Autodesk Fusion 360 part; units mm, degrees
(part 2 of 3)
  spline S78 degree 3 poles (62.3363, -64.3486) (62.4149, -64.4998) (62.5733, -64.8047) (62.5949, -65.1477) (62.6057, -65.3206) knots 0 0 0 0 0.050517 0.101865 0.101865 0.101865 0.101865
  spline S79 degree 3 poles (62.6057, -65.3206) (62.5968, -65.4784) (62.5791, -65.7914) (62.4487, -66.0764) (62.384, -66.2176) knots 0 0 0 0 0.046969 0.093127 0.093127 0.093127 0.093127
  spline S80 degree 3 poles (62.384, -66.2176) (62.3034, -66.3494) (62.1421, -66.613) (61.901, -66.8064) (61.7804, -66.9031) knots 0 0 0 0 0.045957 0.091962 0.091962 0.091962 0.091962
  spline S81 degree 3 poles (61.7804, -66.9031) (61.6697, -66.9728) (61.4254, -67.1265) (61.1499, -67.2136) (60.9993, -67.2613) knots 0 0 0 0 0.039078 0.086233 0.086233 0.086233 0.086233
  spline S82 degree 3 poles (60.9993, -67.2613) (60.8294, -67.304) (60.4812, -67.3916) (60.1223, -67.4024) (59.9386, -67.4079) knots 0 0 0 0 0.052412 0.10736 0.10736 0.10736 0.10736
  spline S83 degree 3 poles (59.9386, -67.4079) (59.6696, -67.4001) (59.1592, -67.3852) (58.6718, -67.2339) (58.4413, -67.1623) knots 0 0 0 0 0.0803 0.152356 0.152356 0.152356 0.152356
  spline S84 degree 3 poles (58.4413, -67.1623) (58.2451, -67.0792) (57.88, -66.9245) (57.6132, -66.6324) (57.4898, -66.4973) knots 0 0 0 0 0.063037 0.117311 0.117311 0.117311 0.117311
  spline S85 degree 3 poles (57.4898, -66.4973) (57.3942, -66.3374) (57.1861, -65.9894) (57.1087, -65.5907) (57.0668, -65.3752) knots 0 0 0 0 0.055458 0.120727 0.120727 0.120727 0.120727
  line L43 (57.0668, -65.3752) -> (58.2674, -65.2115)
  spline S86 degree 3 poles (58.2674, -65.2115) (58.3053, -65.3858) (58.3788, -65.7235) (58.6233, -65.9669) (58.7415, -66.0846) knots 0 0 0 0 0.052286 0.10125 0.10125 0.10125 0.10125
  spline S87 degree 3 poles (58.7415, -66.0846) (58.8953, -66.1759) (59.2356, -66.3778) (59.6325, -66.3911) (59.8499, -66.3984) knots 0 0 0 0 0.052851 0.116857 0.116857 0.116857 0.116857
  spline S88 degree 3 poles (59.8499, -66.3984) (60.097, -66.3964) (60.5227, -66.3929) (60.8993, -66.1997) (61.0573, -66.1187) knots 0 0 0 0 0.072813 0.125434 0.125434 0.125434 0.125434
  spline S89 degree 3 poles (61.0573, -66.1187) (61.1626, -66.0255) (61.3619, -65.8492) (61.4006, -65.5873) (61.4188, -65.4638) knots 0 0 0 0 0.040702 0.076975 0.076975 0.076975 0.076975
  spline S90 degree 3 poles (61.4188, -65.4638) (61.4125, -65.3861) (61.3997, -65.2299) (61.3125, -65.0996) (61.2688, -65.0341) knots 0 0 0 0 0.022989 0.046195 0.046195 0.046195 0.046195
  spline S91 degree 3 poles (61.2688, -65.0341) (61.2076, -64.9695) (61.0738, -64.828) (60.8952, -64.7494) (60.7981, -64.7067) knots 0 0 0 0 0.026422 0.05785 0.05785 0.05785 0.05785
  spline S92 degree 3 poles (60.7981, -64.7067) (60.6772, -64.6686) (60.3182, -64.5555) (59.9546, -64.4577) (59.7135, -64.3929) knots 0 0 0 0 0.038027 0.112916 0.112916 0.112916 0.112916
  spline S93 degree 3 poles (59.7135, -64.3929) (59.3426, -64.2944) (58.7281, -64.1312) (58.132, -63.9107) (57.8956, -63.8233) knots 0 0 0 0 0.115025 0.190592 0.190592 0.190592 0.190592
  spline S94 degree 3 poles (57.8956, -63.8233) (57.7344, -63.7427) (57.419, -63.5851) (57.1962, -63.3121) (57.0873, -63.1787) knots 0 0 0 0 0.053404 0.104439 0.104439 0.104439 0.104439
  spline S95 degree 3 poles (57.0873, -63.1787) (57.0018, -63.0242) (56.8213, -62.6979) (56.8034, -62.3247) (56.794, -62.1282) knots 0 0 0 0 0.052263 0.110368 0.110368 0.110368 0.110368
  spline S96 degree 3 poles (56.794, -62.1282) (56.8098, -61.9253) (56.8419, -61.513) (57.0477, -61.1542) (57.1521, -60.972) knots 0 0 0 0 0.06027 0.122395 0.122395 0.122395 0.122395
  spline S97 degree 3 poles (57.1521, -60.972) (57.2883, -60.8) (57.5701, -60.4439) (57.9758, -60.2389) (58.1855, -60.133) knots 0 0 0 0 0.065008 0.13454 0.13454 0.13454 0.13454
  spline S98 degree 3 poles (58.1855, -60.133) (58.423, -60.0465) (58.9163, -59.8668) (59.4412, -59.8467) (59.7135, -59.8363) knots 0 0 0 0 0.075327 0.156499 0.156499 0.156499 0.156499
  spline S99 degree 3 poles (20.9754, -57.3431) (21.1267, -57.2606) (21.4411, -57.089) (21.7992, -57.0699) (21.985, -57.06) knots 0 0 0 0 0.051013 0.10604 0.10604 0.10604 0.10604
  spline S100 degree 3 poles (21.985, -57.06) (22.1109, -57.0678) (22.3808, -57.0844) (22.6387, -57.1664) (22.7763, -57.2101) knots 0 0 0 0 0.037705 0.08081 0.08081 0.08081 0.08081
  line L44 (22.7763, -57.2101) -> (22.9127, -58.3629)
  spline S101 degree 3 poles (22.9127, -58.3629) (22.7877, -58.3311) (22.5569, -58.2724) (22.3192, -58.2596) (22.2101, -58.2538) knots 0 0 0 0 0.038566 0.071252 0.071252 0.071252 0.071252
  spline S102 degree 3 poles (22.2101, -58.2538) (22.0855, -58.2569) (21.8584, -58.2625) (21.6495, -58.3505) (21.5553, -58.3902) knots 0 0 0 0 0.036993 0.067414 0.067414 0.067414 0.067414
  spline S103 degree 3 poles (21.5553, -58.3902) (21.4768, -58.4406) (21.3185, -58.5424) (21.2084, -58.6951) (21.1528, -58.7722) knots 0 0 0 0 0.027696 0.055929 0.055929 0.055929 0.055929
  spline S104 degree 3 poles (21.1528, -58.7722) (21.1006, -58.8784) (20.9551, -59.1744) (20.847, -59.4862) (20.7776, -59.6862) knots 0 0 0 0 0.035471 0.098882 0.098882 0.098882 0.098882
  spline S105 degree 3 poles (20.7776, -59.6862) (20.763, -59.7283) (20.7281, -59.8289) (20.6904, -59.9285) (20.6685, -59.9864) knots 0 0 0 0 0.013376 0.031938 0.031938 0.031938 0.031938
  line L45 (20.6685, -59.9864) -> (23.4175, -67.2442)
  line L46 (23.4175, -67.2442) -> (22.0941, -67.2442)
  line L47 (22.0941, -67.2442) -> (20.5866, -63.0491)
  spline S106 degree 3 poles (20.5866, -63.0491) (20.4908, -62.7773) (20.2958, -62.2242) (20.1404, -61.6586) (20.0614, -61.3711) knots 0 0 0 0 0.086446 0.175881 0.175881 0.175881 0.175881
  spline S107 degree 3 poles (20.0614, -61.3711) (19.9877, -61.6507) (19.841, -62.2076) (19.6511, -62.7512) (19.5566, -63.0218) knots 0 0 0 0 0.08672 0.172679 0.172679 0.172679 0.172679
  line L48 (19.5566, -63.0218) -> (18.0082, -67.2442)
  line L49 (18.0082, -67.2442) -> (16.7804, -67.2442)
  line L50 (16.7804, -67.2442) -> (19.5362, -59.8772)
  spline S108 degree 3 poles (19.5362, -59.8772) (19.6613, -59.5386) (19.8674, -58.9806) (20.1242, -58.4442) (20.2251, -58.2333) knots 0 0 0 0 0.10821 0.178327 0.178327 0.178327 0.178327
  spline S109 degree 3 poles (20.2251, -58.2333) (20.3318, -58.049) (20.5295, -57.7072) (20.8348, -57.4579) (20.9754, -57.3431) knots 0 0 0 0 0.06326 0.117278 0.117278 0.117278 0.117278
  spline S110 degree 3 poles (36.7462, -60.8458) (36.5323, -60.8585) (36.1186, -60.883) (35.7645, -61.0971) (35.5935, -61.2005) knots 0 0 0 0 0.06321 0.122239 0.122239 0.122239 0.122239
  spline S111 degree 3 poles (35.5935, -61.2005) (35.4392, -61.3461) (35.1015, -61.6649) (34.9297, -62.0977) (34.8363, -62.3329) knots 0 0 0 0 0.062866 0.137684 0.137684 0.137684 0.137684
  line L51 (34.8363, -62.3329) -> (33.5675, -62.176)
  spline S112 degree 3 poles (33.5675, -62.176) (33.6841, -61.8298) (33.9097, -61.1599) (34.4286, -60.6814) (34.6794, -60.4502) knots 0 0 0 0 0.107617 0.208258 0.208258 0.208258 0.208258
  spline S113 degree 3 poles (34.6794, -60.4502) (34.9797, -60.2713) (35.6172, -59.8915) (36.3601, -59.8554) (36.7531, -59.8363) knots 0 0 0 0 0.103262 0.219221 0.219221 0.219221 0.219221
  spline S114 degree 3 poles (36.7531, -59.8363) (37.2475, -59.8691) (38.193, -59.9317) (38.9245, -60.5298) (39.2735, -60.8151) knots 0 0 0 0 0.144566 0.276454 0.276454 0.276454 0.276454
  spline S115 degree 3 poles (39.2735, -60.8151) (39.5447, -61.1934) (40.1306, -62.0107) (40.1787, -63.0191) (40.2046, -63.5607) knots 0 0 0 0 0.136756 0.295447 0.295447 0.295447 0.295447
  spline S116 degree 3 poles (40.2046, -63.5607) (40.1791, -64.1203) (40.1317, -65.159) (39.5374, -66.0071) (39.2633, -66.3984) knots 0 0 0 0 0.164043 0.304496 0.304496 0.304496 0.304496
  spline S117 degree 3 poles (39.2633, -66.3984) (38.9205, -66.6928) (38.2184, -67.2959) (37.2943, -67.37) (36.8213, -67.4079) knots 0 0 0 0 0.131993 0.270399 0.270399 0.270399 0.270399
  spline S118 degree 3 poles (36.8213, -67.4079) (36.3624, -67.3702) (35.4633, -67.2963) (34.7814, -66.7073) (34.4475, -66.4188) knots 0 0 0 0 0.134288 0.263167 0.263167 0.263167 0.263167
  spline S119 degree 3 poles (34.4475, -66.4188) (34.1793, -66.0352) (33.5976, -65.2031) (33.5515, -64.1847) (33.5266, -63.6357) knots 0 0 0 0 0.137617 0.298549 0.298549 0.298549 0.298549
  spline S120 degree 3 poles (33.5266, -63.6357) (33.527, -63.5903) (33.5281, -63.4811) (33.5315, -63.372) (33.5334, -63.3083) knots 0 0 0 0 0.013644 0.03275 0.03275 0.03275 0.03275
  line L52 (33.5334, -63.3083) -> (38.9359, -63.3083)
  spline S121 degree 3 poles (38.9359, -63.3083) (38.9004, -62.9446) (38.8349, -62.2735) (38.441, -61.7294) (38.2606, -61.4802) knots 0 0 0 0 0.107325 0.198019 0.198019 0.198019 0.198019
  spline S122 degree 3 poles (38.2606, -61.4802) (38.0443, -61.2952) (37.6078, -60.9217) (37.0352, -60.8713) (36.7462, -60.8458) knots 0 0 0 0 0.083167 0.167884 0.167884 0.167884 0.167884
  line L53 (26.1596, -63.7926) -> (26.1596, -60)
  line L54 (26.1596, -60) -> (27.3875, -60)
  line L55 (27.3875, -60) -> (27.3875, -67.2442)
  line L56 (27.3875, -67.2442) -> (26.2824, -67.2442)
  line L57 (26.2824, -67.2442) -> (26.2824, -66.146)
  spline S123 degree 3 poles (26.2824, -66.146) (26.1593, -66.3691) (25.9499, -66.7486) (25.6323, -67.0416) (25.5014, -67.1623) knots 0 0 0 0 0.075788 0.128905 0.128905 0.128905 0.128905
  spline S124 degree 3 poles (25.5014, -67.1623) (25.3792, -67.234) (25.1356, -67.3768) (24.8539, -67.3976) (24.7135, -67.4079) knots 0 0 0 0 0.04187 0.083509 0.083509 0.083509 0.083509
  spline S125 degree 3 poles (24.7135, -67.4079) (24.5008, -67.3883) (24.0525, -67.347) (23.6586, -67.1276) (23.4516, -67.0123) knots 0 0 0 0 0.063362 0.133551 0.133551 0.133551 0.133551
  line L58 (23.4516, -67.0123) -> (23.8745, -65.8731)
  spline S126 degree 3 poles (23.8745, -65.8731) (24.0214, -65.9507) (24.304, -66.0999) (24.6221, -66.1264) (24.7749, -66.1392) knots 0 0 0 0 0.049244 0.094752 0.094752 0.094752 0.094752
  spline S127 degree 3 poles (24.7749, -66.1392) (24.9056, -66.1291) (25.1669, -66.1089) (25.3876, -65.9676) (25.498, -65.897) knots 0 0 0 0 0.038676 0.077317 0.077317 0.077317 0.077317
  spline S128 degree 3 poles (25.498, -65.897) (25.5978, -65.8064) (25.8038, -65.6193) (25.9036, -65.3592) (25.955, -65.2251) knots 0 0 0 0 0.039866 0.082277 0.082277 0.082277 0.082277
  spline S129 degree 3 poles (25.955, -65.2251) (26.0146, -64.9978) (26.1379, -64.5283) (26.1522, -64.043) (26.1596, -63.7926) knots 0 0 0 0 0.070251 0.145119 0.145119 0.145119 0.145119
  line L59 (30.8117, -63.7926) -> (30.8117, -60)
  line L60 (30.8117, -60) -> (32.0396, -60)
  line L61 (32.0396, -60) -> (32.0396, -67.2442)
  line L62 (32.0396, -67.2442) -> (30.9345, -67.2442)
  line L63 (30.9345, -67.2442) -> (30.9345, -66.146)
  spline S130 degree 3 poles (30.9345, -66.146) (30.8114, -66.3691) (30.6021, -66.7486) (30.2844, -67.0416) (30.1535, -67.1623) knots 0 0 0 0 0.075788 0.128905 0.128905 0.128905 0.128905
  spline S131 degree 3 poles (30.1535, -67.1623) (30.0313, -67.234) (29.7877, -67.3768) (29.5061, -67.3976) (29.3656, -67.4079) knots 0 0 0 0 0.04187 0.083509 0.083509 0.083509 0.083509
  spline S132 degree 3 poles (29.3656, -67.4079) (29.1529, -67.3883) (28.7046, -67.347) (28.3107, -67.1276) (28.1037, -67.0123) knots 0 0 0 0 0.063362 0.133551 0.133551 0.133551 0.133551
  line L64 (28.1037, -67.0123) -> (28.5266, -65.8731)
  spline S133 degree 3 poles (28.5266, -65.8731) (28.6735, -65.9507) (28.9561, -66.0999) (29.2742, -66.1264) (29.427, -66.1392) knots 0 0 0 0 0.049244 0.094752 0.094752 0.094752 0.094752
  spline S134 degree 3 poles (29.427, -66.1392) (29.5577, -66.1291) (29.819, -66.1089) (30.0398, -65.9676) (30.1501, -65.897) knots 0 0 0 0 0.038676 0.077317 0.077317 0.077317 0.077317
  spline S135 degree 3 poles (30.1501, -65.897) (30.2499, -65.8064) (30.456, -65.6193) (30.5557, -65.3592) (30.6071, -65.2251) knots 0 0 0 0 0.039866 0.082277 0.082277 0.082277 0.082277
  spline S136 degree 3 poles (30.6071, -65.2251) (30.6668, -64.9978) (30.79, -64.5283) (30.8043, -64.043) (30.8117, -63.7926) knots 0 0 0 0 0.070251 0.145119 0.145119 0.145119 0.145119
  spline S137 degree 3 poles (44.4202, -59.8363) (44.825, -59.8815) (45.6372, -59.9721) (46.1668, -60.5949) (46.4325, -60.9072) knots 0 0 0 0 0.117518 0.235779 0.235779 0.235779 0.235779
  line L65 (46.4325, -60.9072) -> (46.4325, -60)
  line L66 (46.4325, -60) -> (47.5716, -60)
  line L67 (47.5716, -60) -> (47.5716, -70)
  line L68 (47.5716, -70) -> (46.3438, -70)
  line L69 (46.3438, -70) -> (46.3438, -66.4325)
  spline S138 degree 3 poles (46.3438, -66.4325) (46.0686, -66.717) (45.5235, -67.2806) (44.7446, -67.3657) (44.3588, -67.4079) knots 0 0 0 0 0.114828 0.227492 0.227492 0.227492 0.227492
  spline S139 degree 3 poles (44.3588, -67.4079) (44.1395, -67.3969) (43.7032, -67.3751) (43.296, -67.2171) (43.0935, -67.1385) knots 0 0 0 0 0.065406 0.130119 0.130119 0.130119 0.130119
  spline S140 degree 3 poles (43.0935, -67.1385) (42.9042, -67.0407) (42.5308, -66.8478) (42.2498, -66.5354) (42.1112, -66.3813) knots 0 0 0 0 0.063318 0.124938 0.124938 0.124938 0.124938
  spline S141 degree 3 poles (42.1112, -66.3813) (41.9884, -66.2062) (41.733, -65.842) (41.5846, -65.4225) (41.5075, -65.2046) knots 0 0 0 0 0.06384 0.132796 0.132796 0.132796 0.132796
  spline S142 degree 3 poles (41.5075, -65.2046) (41.4438, -64.9684) (41.3138, -64.4858) (41.2975, -63.9862) (41.2892, -63.7312) knots 0 0 0 0 0.073138 0.149391 0.149391 0.149391 0.149391
  spline S143 degree 3 poles (41.2892, -63.7312) (41.313, -63.1631) (41.3567, -62.1148) (41.942, -61.2492) (42.2101, -60.8527) knots 0 0 0 0 0.166673 0.307548 0.307548 0.307548 0.307548
  spline S144 degree 3 poles (42.2101, -60.8527) (42.5285, -60.5562) (43.1542, -59.9737) (44.0032, -59.8815) (44.4202, -59.8363) knots 0 0 0 0 0.126774 0.249154 0.249154 0.249154 0.249154
  line L70 (54.1064, -60.7503) -> (54.1064, -57.2237)
  line L71 (54.1064, -57.2237) -> (55.3342, -57.2237)
  line L72 (55.3342, -57.2237) -> (55.3342, -67.2442)
  line L73 (55.3342, -67.2442) -> (54.2156, -67.2442)
  line L74 (54.2156, -67.2442) -> (54.2156, -66.3029)
  spline S145 degree 3 poles (54.2156, -66.3029) (54.0836, -66.4732) (53.8311, -66.7989) (53.4864, -67.0242) (53.322, -67.1317) knots 0 0 0 0 0.064121 0.122635 0.122635 0.122635 0.122635
  spline S146 degree 3 poles (53.322, -67.1317) (53.1411, -67.2122) (52.7572, -67.383) (52.3369, -67.3993) (52.1146, -67.4079) knots 0 0 0 0 0.05885 0.124867 0.124867 0.124867 0.124867
  spline S147 degree 3 poles (52.1146, -67.4079) (51.8172, -67.3898) (51.2349, -67.3544) (50.7263, -67.0697) (50.4775, -66.9304) knots 0 0 0 0 0.088125 0.1725 0.1725 0.1725 0.1725
  spline S148 degree 3 poles (50.4775, -66.9304) (50.2541, -66.7514) (49.7954, -66.3838) (49.5384, -65.8546) (49.4065, -65.5832) knots 0 0 0 0 0.084775 0.174028 0.174028 0.174028 0.174028
  spline S149 degree 3 poles (49.4065, -65.5832) (49.3011, -65.2823) (49.0849, -64.6652) (49.0585, -64.0115) (49.045, -63.6767) knots 0 0 0 0 0.095097 0.195012 0.195012 0.195012 0.195012
  spline S150 degree 3 poles (49.045, -63.6767) (49.0593, -63.3207) (49.0869, -62.6319) (49.3277, -61.9865) (49.4441, -61.6746) knots 0 0 0 0 0.106115 0.205298 0.205298 0.205298 0.205298
  spline S151 degree 3 poles (49.4441, -61.6746) (49.5892, -61.3971) (49.8729, -60.8544) (50.3638, -60.489) (50.6037, -60.3104) knots 0 0 0 0 0.092606 0.181113 0.181113 0.181113 0.181113
  spline S152 degree 3 poles (50.6037, -60.3104) (50.8579, -60.1721) (51.3577, -59.9003) (51.9247, -59.8574) (52.2033, -59.8363) knots 0 0 0 0 0.085739 0.168532 0.168532 0.168532 0.168532
  spline S153 degree 3 poles (52.2033, -59.8363) (52.4003, -59.8458) (52.7837, -59.8644) (53.1344, -60.0199) (53.3049, -60.0955) knots 0 0 0 0 0.058596 0.114043 0.114043 0.114043 0.114043
  spline S154 degree 3 poles (53.3049, -60.0955) (53.459, -60.186) (53.7601, -60.3629) (53.9928, -60.6232) (54.1064, -60.7503) knots 0 0 0 0 0.053233 0.104061 0.104061 0.104061 0.104061
  line L75 (63.8336, -60) -> (65.116, -60)
  spline S155 degree 3 poles (65.116, -60) (65.1743, -60.1364) (65.2968, -60.4229) (65.3393, -60.7318) (65.3615, -60.8936) knots 0 0 0 0 0.04431 0.093043 0.093043 0.093043 0.093043
  spline S156 degree 3 poles (65.3615, -60.8936) (65.578, -60.718) (65.982, -60.3903) (66.4551, -60.175) (66.6746, -60.075) knots 0 0 0 0 0.083222 0.155292 0.155292 0.155292 0.155292
  spline S157 degree 3 poles (66.6746, -60.075) (66.8909, -60.0054) (67.3311, -59.8636) (67.7934, -59.8455) (68.0286, -59.8363) knots 0 0 0 0 0.067806 0.138063 0.138063 0.138063 0.138063
  spline S158 degree 3 poles (68.0286, -59.8363) (68.392, -59.8508) (69.06, -59.8776) (69.6119, -60.2497) (69.8636, -60.4195) knots 0 0 0 0 0.106562 0.195931 0.195931 0.195931 0.195931
  spline S159 degree 3 poles (69.8636, -60.4195) (70.0506, -60.6293) (70.4295, -61.0545) (70.4795, -61.6224) (70.5048, -61.91) knots 0 0 0 0 0.082003 0.166167 0.166167 0.166167 0.166167
  spline S160 degree 3 poles (70.5048, -61.91) (70.4953, -62.0823) (70.4767, -62.4219) (70.3332, -62.7302) (70.2626, -62.882) knots 0 0 0 0 0.051263 0.100997 0.100997 0.100997 0.100997
  spline S161 degree 3 poles (70.2626, -62.882) (70.1767, -63.0207) (70.0073, -63.294) (69.7533, -63.491) (69.6282, -63.588) knots 0 0 0 0 0.04852 0.095596 0.095596 0.095596 0.095596
  spline S162 degree 3 poles (69.6282, -63.588) (69.4919, -63.6717) (69.2141, -63.8422) (68.9032, -63.9404) (68.7449, -63.9904) knots 0 0 0 0 0.047794 0.097396 0.097396 0.097396 0.097396
  spline S163 degree 3 poles (68.7449, -63.9904) (68.594, -64.0237) (68.2334, -64.1033) (67.8668, -64.1484) (67.6535, -64.1746) knots 0 0 0 0 0.046321 0.110737 0.110737 0.110737 0.110737
  spline S164 degree 3 poles (67.6535, -64.1746) (67.2207, -64.227) (66.4804, -64.3166) (65.7622, -64.5151) (65.4638, -64.5975) knots 0 0 0 0 0.130548 0.223278 0.223278 0.223278 0.223278
  spline S165 degree 3 poles (65.4638, -64.5975) (65.4619, -64.6663) (65.4589, -64.7732) (65.4575, -64.8801) (65.457, -64.9181) knots 0 0 0 0 0.020641 0.032068 0.032068 0.032068 0.032068
  spline S166 degree 3 poles (65.457, -64.9181) (65.4619, -65.14) (65.4706, -65.5312) (65.7039, -65.8412) (65.8049, -65.9754) knots 0 0 0 0 0.064538 0.113796 0.113796 0.113796 0.113796
  spline S167 degree 3 poles (65.8049, -65.9754) (65.9945, -66.0965) (66.4185, -66.3671) (66.9238, -66.3829) (67.2033, -66.3915) knots 0 0 0 0 0.066297 0.148303 0.148303 0.148303 0.148303
  spline S168 degree 3 poles (67.2033, -66.3915) (67.4598, -66.3875) (67.9106, -66.3805) (68.3101, -66.1761) (68.4823, -66.088) knots 0 0 0 0 0.075671 0.132995 0.132995 0.132995 0.132995
  spline S169 degree 3 poles (68.4823, -66.088) (68.6137, -65.9549) (68.9118, -65.6531) (69.0279, -65.2429) (69.0928, -65.0136) knots 0 0 0 0 0.055278 0.125347 0.125347 0.125347 0.125347
  line L76 (69.0928, -65.0136) -> (70.2933, -65.1774)
  spline S170 degree 3 poles (70.2933, -65.1774) (70.2348, -65.4156) (70.1252, -65.8615) (69.8722, -66.2441) (69.7544, -66.4222) knots 0 0 0 0 0.072951 0.136549 0.136549 0.136549 0.136549
  spline S171 degree 3 poles (69.7544, -66.4222) (69.6092, -66.5733) (69.3008, -66.8942) (68.8882, -67.0629) (68.6698, -67.1521) knots 0 0 0 0 0.062163 0.132021 0.132021 0.132021 0.132021
  spline S172 degree 3 poles (68.6698, -67.1521) (68.4163, -67.2267) (67.88, -67.3844) (67.3208, -67.3998) (67.0259, -67.4079) knots 0 0 0 0 0.078936 0.166992 0.166992 0.166992 0.166992
  spline S173 degree 3 poles (67.0259, -67.4079) (66.7436, -67.4032) (66.2312, -67.3945) (65.7393, -67.2531) (65.5184, -67.1896) knots 0 0 0 0 0.084249 0.152908 0.152908 0.152908 0.152908
  spline S174 degree 3 poles (65.5184, -67.1896) (65.3435, -67.1185) (65.0241, -66.9886) (64.7773, -66.7489) (64.6658, -66.6405) knots 0 0 0 0 0.056018 0.102261 0.102261 0.102261 0.102261
  spline S175 degree 3 poles (64.6658, -66.6405) (64.5809, -66.5193) (64.4024, -66.2644) (64.3246, -65.9629) (64.2838, -65.8049) knots 0 0 0 0 0.044034 0.092543 0.092543 0.092543 0.092543
  spline S176 degree 3 poles (64.2838, -65.8049) (64.2661, -65.6584) (64.2206, -65.2825) (64.2217, -64.9037) (64.2224, -64.6726) knots 0 0 0 0 0.044238 0.113491 0.113491 0.113491 0.113491
  line L77 (64.2224, -64.6726) -> (64.2224, -63.0355)
  spline S177 degree 3 poles (64.2224, -63.0355) (64.2252, -62.5692) (64.2296, -61.8459) (64.1664, -61.1257) (64.1439, -60.8697) knots 0 0 0 0 0.139765 0.216814 0.216814 0.216814 0.216814
  spline S178 degree 3 poles (64.1439, -60.8697) (64.1111, -60.7195) (64.0447, -60.4164) (63.9044, -60.1396) (63.8336, -60) knots 0 0 0 0 0.045934 0.092677 0.092677 0.092677 0.092677
  line L78 (-40, 0) -> (-70, 0) construction
  line L79 (-70, 0) -> (-70, -10) construction
  line L80 (-70, -10) -> (-40, -10) construction
  line L81 (-40, -10) -> (-40, 0) construction
  dimension "d61" = 9
  dimension "d62" = 0
  text T0 "L298N" font "Arial" height 9 align left top in box 30 x 10 at (-40, 0) x (-1, 0) y (0, -1) spacing 1 kerned
extrude "Estrusione4" cut sketch "Schizzo4" against normal blind 1 text T0
sketch "Schizzo5" plane through (0, 0, 3) normal (0, 0, 1) x (-1, 0, 0)
  line L0 (63.8336, -60) -> (65.116, -60)
  spline S0 degree 3 poles (65.116, -60) (65.1743, -60.1364) (65.2968, -60.4229) (65.3393, -60.7318) (65.3615, -60.8936) knots 0 0 0 0 0.04431 0.093043 0.093043 0.093043 0.093043
  spline S1 degree 3 poles (65.3615, -60.8936) (65.578, -60.718) (65.982, -60.3903) (66.4551, -60.175) (66.6746, -60.075) knots 0 0 0 0 0.083222 0.155292 0.155292 0.155292 0.155292
  spline S2 degree 3 poles (66.6746, -60.075) (66.8909, -60.0054) (67.3311, -59.8636) (67.7934, -59.8455) (68.0286, -59.8363) knots 0 0 0 0 0.067806 0.138063 0.138063 0.138063 0.138063
  spline S3 degree 3 poles (68.0286, -59.8363) (68.392, -59.8508) (69.06, -59.8776) (69.6119, -60.2497) (69.8636, -60.4195) knots 0 0 0 0 0.106562 0.195931 0.195931 0.195931 0.195931
  spline S4 degree 3 poles (69.8636, -60.4195) (70.0506, -60.6293) (70.4295, -61.0545) (70.4795, -61.6224) (70.5048, -61.91) knots 0 0 0 0 0.082003 0.166167 0.166167 0.166167 0.166167
  spline S5 degree 3 poles (70.5048, -61.91) (70.4953, -62.0823) (70.4767, -62.4219) (70.3332, -62.7302) (70.2626, -62.882) knots 0 0 0 0 0.051263 0.100997 0.100997 0.100997 0.100997
  spline S6 degree 3 poles (70.2626, -62.882) (70.1767, -63.0207) (70.0073, -63.294) (69.7533, -63.491) (69.6282, -63.588) knots 0 0 0 0 0.04852 0.095596 0.095596 0.095596 0.095596
  spline S7 degree 3 poles (69.6282, -63.588) (69.4919, -63.6717) (69.2141, -63.8422) (68.9032, -63.9404) (68.7449, -63.9904) knots 0 0 0 0 0.047794 0.097396 0.097396 0.097396 0.097396
  spline S8 degree 3 poles (68.7449, -63.9904) (68.594, -64.0237) (68.2334, -64.1033) (67.8668, -64.1484) (67.6535, -64.1746) knots 0 0 0 0 0.046321 0.110737 0.110737 0.110737 0.110737
  spline S9 degree 3 poles (67.6535, -64.1746) (67.2207, -64.227) (66.4804, -64.3166) (65.7622, -64.5151) (65.4638, -64.5975) knots 0 0 0 0 0.130548 0.223278 0.223278 0.223278 0.223278
  spline S10 degree 3 poles (65.4638, -64.5975) (65.4619, -64.6663) (65.4589, -64.7732) (65.4575, -64.8801) (65.457, -64.9181) knots 0 0 0 0 0.020641 0.032068 0.032068 0.032068 0.032068
  spline S11 degree 3 poles (65.457, -64.9181) (65.4619, -65.14) (65.4706, -65.5312) (65.7039, -65.8412) (65.8049, -65.9754) knots 0 0 0 0 0.064538 0.113796 0.113796 0.113796 0.113796
  spline S12 degree 3 poles (65.8049, -65.9754) (65.9945, -66.0965) (66.4185, -66.3671) (66.9238, -66.3829) (67.2033, -66.3915) knots 0 0 0 0 0.066297 0.148303 0.148303 0.148303 0.148303
  spline S13 degree 3 poles (67.2033, -66.3915) (67.4598, -66.3875) (67.9106, -66.3805) (68.3101, -66.1761) (68.4823, -66.088) knots 0 0 0 0 0.075671 0.132995 0.132995 0.132995 0.132995
  spline S14 degree 3 poles (68.4823, -66.088) (68.6137, -65.9549) (68.9118, -65.6531) (69.0279, -65.2429) (69.0928, -65.0136) knots 0 0 0 0 0.055278 0.125347 0.125347 0.125347 0.125347
  line L1 (69.0928, -65.0136) -> (70.2933, -65.1774)
  spline S15 degree 3 poles (70.2933, -65.1774) (70.2348, -65.4156) (70.1252, -65.8615) (69.8722, -66.2441) (69.7544, -66.4222) knots 0 0 0 0 0.072951 0.136549 0.136549 0.136549 0.136549
  spline S16 degree 3 poles (69.7544, -66.4222) (69.6092, -66.5733) (69.3008, -66.8942) (68.8882, -67.0629) (68.6698, -67.1521) knots 0 0 0 0 0.062163 0.132021 0.132021 0.132021 0.132021
  spline S17 degree 3 poles (68.6698, -67.1521) (68.4163, -67.2267) (67.88, -67.3844) (67.3208, -67.3998) (67.0259, -67.4079) knots 0 0 0 0 0.078936 0.166992 0.166992 0.166992 0.166992
  spline S18 degree 3 poles (67.0259, -67.4079) (66.7436, -67.4032) (66.2312, -67.3945) (65.7393, -67.2531) (65.5184, -67.1896) knots 0 0 0 0 0.084249 0.152908 0.152908 0.152908 0.152908
  spline S19 degree 3 poles (65.5184, -67.1896) (65.3435, -67.1185) (65.0241, -66.9886) (64.7773, -66.7489) (64.6658, -66.6405) knots 0 0 0 0 0.056018 0.102261 0.102261 0.102261 0.102261
  spline S20 degree 3 poles (64.6658, -66.6405) (64.5809, -66.5193) (64.4024, -66.2644) (64.3246, -65.9629) (64.2838, -65.8049) knots 0 0 0 0 0.044034 0.092543 0.092543 0.092543 0.092543
  spline S21 degree 3 poles (64.2838, -65.8049) (64.2661, -65.6584) (64.2206, -65.2825) (64.2217, -64.9037) (64.2224, -64.6726) knots 0 0 0 0 0.044238 0.113491 0.113491 0.113491 0.113491
  line L2 (64.2224, -64.6726) -> (64.2224, -63.0355)
  spline S22 degree 3 poles (64.2224, -63.0355) (64.2252, -62.5692) (64.2296, -61.8459) (64.1664, -61.1257) (64.1439, -60.8697) knots 0 0 0 0 0.139765 0.216814 0.216814 0.216814 0.216814
  spline S23 degree 3 poles (64.1439, -60.8697) (64.1111, -60.7195) (64.0447, -60.4164) (63.9044, -60.1396) (63.8336, -60) knots 0 0 0 0 0.045934 0.092677 0.092677 0.092677 0.092677
  line L3 (54.1064, -60.7503) -> (54.1064, -57.2237)
  line L4 (54.1064, -57.2237) -> (55.3342, -57.2237)
  line L5 (55.3342, -57.2237) -> (55.3342, -67.2442)
  line L6 (55.3342, -67.2442) -> (54.2156, -67.2442)
  line L7 (54.2156, -67.2442) -> (54.2156, -66.3029)
  spline S24 degree 3 poles (54.2156, -66.3029) (54.0836, -66.4732) (53.8311, -66.7989) (53.4864, -67.0242) (53.322, -67.1317) knots 0 0 0 0 0.064121 0.122635 0.122635 0.122635 0.122635
  spline S25 degree 3 poles (53.322, -67.1317) (53.1411, -67.2122) (52.7572, -67.383) (52.3369, -67.3993) (52.1146, -67.4079) knots 0 0 0 0 0.05885 0.124867 0.124867 0.124867 0.124867
  spline S26 degree 3 poles (52.1146, -67.4079) (51.8172, -67.3898) (51.2349, -67.3544) (50.7263, -67.0697) (50.4775, -66.9304) knots 0 0 0 0 0.088125 0.1725 0.1725 0.1725 0.1725
  spline S27 degree 3 poles (50.4775, -66.9304) (50.2541, -66.7514) (49.7954, -66.3838) (49.5384, -65.8546) (49.4065, -65.5832) knots 0 0 0 0 0.084775 0.174028 0.174028 0.174028 0.174028
  spline S28 degree 3 poles (49.4065, -65.5832) (49.3011, -65.2823) (49.0849, -64.6652) (49.0585, -64.0115) (49.045, -63.6767) knots 0 0 0 0 0.095097 0.195012 0.195012 0.195012 0.195012
  spline S29 degree 3 poles (49.045, -63.6767) (49.0593, -63.3207) (49.0869, -62.6319) (49.3277, -61.9865) (49.4441, -61.6746) knots 0 0 0 0 0.106115 0.205298 0.205298 0.205298 0.205298
  spline S30 degree 3 poles (49.4441, -61.6746) (49.5892, -61.3971) (49.8729, -60.8544) (50.3638, -60.489) (50.6037, -60.3104) knots 0 0 0 0 0.092606 0.181113 0.181113 0.181113 0.181113
  spline S31 degree 3 poles (50.6037, -60.3104) (50.8579, -60.1721) (51.3577, -59.9003) (51.9247, -59.8574) (52.2033, -59.8363) knots 0 0 0 0 0.085739 0.168532 0.168532 0.168532 0.168532
  spline S32 degree 3 poles (52.2033, -59.8363) (52.4003, -59.8458) (52.7837, -59.8644) (53.1344, -60.0199) (53.3049, -60.0955) knots 0 0 0 0 0.058596 0.114043 0.114043 0.114043 0.114043
  spline S33 degree 3 poles (53.3049, -60.0955) (53.459, -60.186) (53.7601, -60.3629) (53.9928, -60.6232) (54.1064, -60.7503) knots 0 0 0 0 0.053233 0.104061 0.104061 0.104061 0.104061
  spline S34 degree 3 poles (44.4202, -59.8363) (44.825, -59.8815) (45.6372, -59.9721) (46.1668, -60.5949) (46.4325, -60.9072) knots 0 0 0 0 0.117518 0.235779 0.235779 0.235779 0.235779
  line L8 (46.4325, -60.9072) -> (46.4325, -60)
  line L9 (46.4325, -60) -> (47.5716, -60)
  line L10 (47.5716, -60) -> (47.5716, -70)
  line L11 (47.5716, -70) -> (46.3438, -70)
  line L12 (46.3438, -70) -> (46.3438, -66.4325)
  spline S35 degree 3 poles (46.3438, -66.4325) (46.0686, -66.717) (45.5235, -67.2806) (44.7446, -67.3657) (44.3588, -67.4079) knots 0 0 0 0 0.114828 0.227492 0.227492 0.227492 0.227492
  spline S36 degree 3 poles (44.3588, -67.4079) (44.1395, -67.3969) (43.7032, -67.3751) (43.296, -67.2171) (43.0935, -67.1385) knots 0 0 0 0 0.065406 0.130119 0.130119 0.130119 0.130119
  spline S37 degree 3 poles (43.0935, -67.1385) (42.9042, -67.0407) (42.5308, -66.8478) (42.2498, -66.5354) (42.1112, -66.3813) knots 0 0 0 0 0.063318 0.124938 0.124938 0.124938 0.124938
  spline S38 degree 3 poles (42.1112, -66.3813) (41.9884, -66.2062) (41.733, -65.842) (41.5846, -65.4225) (41.5075, -65.2046) knots 0 0 0 0 0.06384 0.132796 0.132796 0.132796 0.132796
  spline S39 degree 3 poles (41.5075, -65.2046) (41.4438, -64.9684) (41.3138, -64.4858) (41.2975, -63.9862) (41.2892, -63.7312) knots 0 0 0 0 0.073138 0.149391 0.149391 0.149391 0.149391
  spline S40 degree 3 poles (41.2892, -63.7312) (41.313, -63.1631) (41.3567, -62.1148) (41.942, -61.2492) (42.2101, -60.8527) knots 0 0 0 0 0.166673 0.307548 0.307548 0.307548 0.307548
  spline S41 degree 3 poles (42.2101, -60.8527) (42.5285, -60.5562) (43.1542, -59.9737) (44.0032, -59.8815) (44.4202, -59.8363) knots 0 0 0 0 0.126774 0.249154 0.249154 0.249154 0.249154
  line L13 (30.8117, -63.7926) -> (30.8117, -60)
  line L14 (30.8117, -60) -> (32.0396, -60)
  line L15 (32.0396, -60) -> (32.0396, -67.2442)
  line L16 (32.0396, -67.2442) -> (30.9345, -67.2442)
  line L17 (30.9345, -67.2442) -> (30.9345, -66.146)
  spline S42 degree 3 poles (30.9345, -66.146) (30.8114, -66.3691) (30.6021, -66.7486) (30.2844, -67.0416) (30.1535, -67.1623) knots 0 0 0 0 0.075788 0.128905 0.128905 0.128905 0.128905
  spline S43 degree 3 poles (30.1535, -67.1623) (30.0313, -67.234) (29.7877, -67.3768) (29.5061, -67.3976) (29.3656, -67.4079) knots 0 0 0 0 0.04187 0.083509 0.083509 0.083509 0.083509
  spline S44 degree 3 poles (29.3656, -67.4079) (29.1529, -67.3883) (28.7046, -67.347) (28.3107, -67.1276) (28.1037, -67.0123) knots 0 0 0 0 0.063362 0.133551 0.133551 0.133551 0.133551
  line L18 (28.1037, -67.0123) -> (28.5266, -65.8731)
  spline S45 degree 3 poles (28.5266, -65.8731) (28.6735, -65.9507) (28.9561, -66.0999) (29.2742, -66.1264) (29.427, -66.1392) knots 0 0 0 0 0.049244 0.094752 0.094752 0.094752 0.094752
  spline S46 degree 3 poles (29.427, -66.1392) (29.5577, -66.1291) (29.819, -66.1089) (30.0398, -65.9676) (30.1501, -65.897) knots 0 0 0 0 0.038676 0.077317 0.077317 0.077317 0.077317
  spline S47 degree 3 poles (30.1501, -65.897) (30.2499, -65.8064) (30.456, -65.6193) (30.5557, -65.3592) (30.6071, -65.2251) knots 0 0 0 0 0.039866 0.082277 0.082277 0.082277 0.082277
  spline S48 degree 3 poles (30.6071, -65.2251) (30.6668, -64.9978) (30.79, -64.5283) (30.8043, -64.043) (30.8117, -63.7926) knots 0 0 0 0 0.070251 0.145119 0.145119 0.145119 0.145119
  line L19 (26.1596, -63.7926) -> (26.1596, -60)
  line L20 (26.1596, -60) -> (27.3875, -60)
  line L21 (27.3875, -60) -> (27.3875, -67.2442)
  line L22 (27.3875, -67.2442) -> (26.2824, -67.2442)
  line L23 (26.2824, -67.2442) -> (26.2824, -66.146)
  spline S49 degree 3 poles (26.2824, -66.146) (26.1593, -66.3691) (25.9499, -66.7486) (25.6323, -67.0416) (25.5014, -67.1623) knots 0 0 0 0 0.075788 0.128905 0.128905 0.128905 0.128905
  spline S50 degree 3 poles (25.5014, -67.1623) (25.3792, -67.234) (25.1356, -67.3768) (24.8539, -67.3976) (24.7135, -67.4079) knots 0 0 0 0 0.04187 0.083509 0.083509 0.083509 0.083509
  spline S51 degree 3 poles (24.7135, -67.4079) (24.5008, -67.3883) (24.0525, -67.347) (23.6586, -67.1276) (23.4516, -67.0123) knots 0 0 0 0 0.063362 0.133551 0.133551 0.133551 0.133551
  line L24 (23.4516, -67.0123) -> (23.8745, -65.8731)
  spline S52 degree 3 poles (23.8745, -65.8731) (24.0214, -65.9507) (24.304, -66.0999) (24.6221, -66.1264) (24.7749, -66.1392) knots 0 0 0 0 0.049244 0.094752 0.094752 0.094752 0.094752
  spline S53 degree 3 poles (24.7749, -66.1392) (24.9056, -66.1291) (25.1669, -66.1089) (25.3876, -65.9676) (25.498, -65.897) knots 0 0 0 0 0.038676 0.077317 0.077317 0.077317 0.077317
  spline S54 degree 3 poles (25.498, -65.897) (25.5978, -65.8064) (25.8038, -65.6193) (25.9036, -65.3592) (25.955, -65.2251) knots 0 0 0 0 0.039866 0.082277 0.082277 0.082277 0.082277
  spline S55 degree 3 poles (25.955, -65.2251) (26.0146, -64.9978) (26.1379, -64.5283) (26.1522, -64.043) (26.1596, -63.7926) knots 0 0 0 0 0.070251 0.145119 0.145119 0.145119 0.145119
  spline S56 degree 3 poles (36.7462, -60.8458) (36.5323, -60.8585) (36.1186, -60.883) (35.7645, -61.0971) (35.5935, -61.2005) knots 0 0 0 0 0.06321 0.122239 0.122239 0.122239 0.122239
  spline S57 degree 3 poles (35.5935, -61.2005) (35.4392, -61.3461) (35.1015, -61.6649) (34.9297, -62.0977) (34.8363, -62.3329) knots 0 0 0 0 0.062866 0.137684 0.137684 0.137684 0.137684
  line L25 (34.8363, -62.3329) -> (33.5675, -62.176)
  spline S58 degree 3 poles (33.5675, -62.176) (33.6841, -61.8298) (33.9097, -61.1599) (34.4286, -60.6814) (34.6794, -60.4502) knots 0 0 0 0 0.107617 0.208258 0.208258 0.208258 0.208258
  spline S59 degree 3 poles (34.6794, -60.4502) (34.9797, -60.2713) (35.6172, -59.8915) (36.3601, -59.8554) (36.7531, -59.8363) knots 0 0 0 0 0.103262 0.219221 0.219221 0.219221 0.219221
  spline S60 degree 3 poles (36.7531, -59.8363) (37.2475, -59.8691) (38.193, -59.9317) (38.9245, -60.5298) (39.2735, -60.8151) knots 0 0 0 0 0.144566 0.276454 0.276454 0.276454 0.276454
  spline S61 degree 3 poles (39.2735, -60.8151) (39.5447, -61.1934) (40.1306, -62.0107) (40.1787, -63.0191) (40.2046, -63.5607) knots 0 0 0 0 0.136756 0.295447 0.295447 0.295447 0.295447
  spline S62 degree 3 poles (40.2046, -63.5607) (40.1791, -64.1203) (40.1317, -65.159) (39.5374, -66.0071) (39.2633, -66.3984) knots 0 0 0 0 0.164043 0.304496 0.304496 0.304496 0.304496
  spline S63 degree 3 poles (39.2633, -66.3984) (38.9205, -66.6928) (38.2184, -67.2959) (37.2943, -67.37) (36.8213, -67.4079) knots 0 0 0 0 0.131993 0.270399 0.270399 0.270399 0.270399
  spline S64 degree 3 poles (36.8213, -67.4079) (36.3624, -67.3702) (35.4633, -67.2963) (34.7814, -66.7073) (34.4475, -66.4188) knots 0 0 0 0 0.134288 0.263167 0.263167 0.263167 0.263167
  spline S65 degree 3 poles (34.4475, -66.4188) (34.1793, -66.0352) (33.5976, -65.2031) (33.5515, -64.1847) (33.5266, -63.6357) knots 0 0 0 0 0.137617 0.298549 0.298549 0.298549 0.298549
  spline S66 degree 3 poles (33.5266, -63.6357) (33.527, -63.5903) (33.5281, -63.4811) (33.5315, -63.372) (33.5334, -63.3083) knots 0 0 0 0 0.013644 0.03275 0.03275 0.03275 0.03275
  line L26 (33.5334, -63.3083) -> (38.9359, -63.3083)
  spline S67 degree 3 poles (38.9359, -63.3083) (38.9004, -62.9446) (38.8349, -62.2735) (38.441, -61.7294) (38.2606, -61.4802) knots 0 0 0 0 0.107325 0.198019 0.198019 0.198019 0.198019
  spline S68 degree 3 poles (38.2606, -61.4802) (38.0443, -61.2952) (37.6078, -60.9217) (37.0352, -60.8713) (36.7462, -60.8458) knots 0 0 0 0 0.083167 0.167884 0.167884 0.167884 0.167884
  spline S69 degree 3 poles (20.9754, -57.3431) (21.1267, -57.2606) (21.4411, -57.089) (21.7992, -57.0699) (21.985, -57.06) knots 0 0 0 0 0.051013 0.10604 0.10604 0.10604 0.10604
  spline S70 degree 3 poles (21.985, -57.06) (22.1109, -57.0678) (22.3808, -57.0844) (22.6387, -57.1664) (22.7763, -57.2101) knots 0 0 0 0 0.037705 0.08081 0.08081 0.08081 0.08081
  line L27 (22.7763, -57.2101) -> (22.9127, -58.3629)
  spline S71 degree 3 poles (22.9127, -58.3629) (22.7877, -58.3311) (22.5569, -58.2724) (22.3192, -58.2596) (22.2101, -58.2538) knots 0 0 0 0 0.038566 0.071252 0.071252 0.071252 0.071252
  spline S72 degree 3 poles (22.2101, -58.2538) (22.0855, -58.2569) (21.8584, -58.2625) (21.6495, -58.3505) (21.5553, -58.3902) knots 0 0 0 0 0.036993 0.067414 0.067414 0.067414 0.067414
  spline S73 degree 3 poles (21.5553, -58.3902) (21.4768, -58.4406) (21.3185, -58.5424) (21.2084, -58.6951) (21.1528, -58.7722) knots 0 0 0 0 0.027696 0.055929 0.055929 0.055929 0.055929
  spline S74 degree 3 poles (21.1528, -58.7722) (21.1006, -58.8784) (20.9551, -59.1744) (20.847, -59.4862) (20.7776, -59.6862) knots 0 0 0 0 0.035471 0.098882 0.098882 0.098882 0.098882
  spline S75 degree 3 poles (20.7776, -59.6862) (20.763, -59.7283) (20.7281, -59.8289) (20.6904, -59.9285) (20.6685, -59.9864) knots 0 0 0 0 0.013376 0.031938 0.031938 0.031938 0.031938
  line L28 (20.6685, -59.9864) -> (23.4175, -67.2442)
  line L29 (23.4175, -67.2442) -> (22.0941, -67.2442)
  line L30 (22.0941, -67.2442) -> (20.5866, -63.0491)
  spline S76 degree 3 poles (20.5866, -63.0491) (20.4908, -62.7773) (20.2958, -62.2242) (20.1404, -61.6586) (20.0614, -61.3711) knots 0 0 0 0 0.086446 0.175881 0.175881 0.175881 0.175881
  spline S77 degree 3 poles (20.0614, -61.3711) (19.9877, -61.6507) (19.841, -62.2076) (19.6511, -62.7512) (19.5566, -63.0218) knots 0 0 0 0 0.08672 0.172679 0.172679 0.172679 0.172679
  line L31 (19.5566, -63.0218) -> (18.0082, -67.2442)
  line L32 (18.0082, -67.2442) -> (16.7804, -67.2442)
  line L33 (16.7804, -67.2442) -> (19.5362, -59.8772)
  spline S78 degree 3 poles (19.5362, -59.8772) (19.6613, -59.5386) (19.8674, -58.9806) (20.1242, -58.4442) (20.2251, -58.2333) knots 0 0 0 0 0.10821 0.178327 0.178327 0.178327 0.178327
  spline S79 degree 3 poles (20.2251, -58.2333) (20.3318, -58.049) (20.5295, -57.7072) (20.8348, -57.4579) (20.9754, -57.3431) knots 0 0 0 0 0.06326 0.117278 0.117278 0.117278 0.117278
  spline S80 degree 3 poles (59.7135, -59.8363) (60.139, -59.8483) (60.9071, -59.87) (61.5699, -60.2523) (61.8656, -60.4229) knots 0 0 0 0 0.125264 0.22617 0.22617 0.22617 0.22617
  spline S81 degree 3 poles (61.8656, -60.4229) (62.0917, -60.6523) (62.5721, -61.1398) (62.7279, -61.8083) (62.8104, -62.1623) knots 0 0 0 0 0.09475 0.201391 0.201391 0.201391 0.201391
  line L34 (62.8104, -62.1623) -> (61.5962, -62.3533)
  spline S82 degree 3 poles (61.5962, -62.3533) (61.5514, -62.1282) (61.4663, -61.7006) (61.1679, -61.3844) (61.0266, -61.2347) knots 0 0 0 0 0.067304 0.127814 0.127814 0.127814 0.127814
  spline S83 degree 3 poles (61.0266, -61.2347) (60.8449, -61.1215) (60.4467, -60.8735) (59.9762, -60.8556) (59.7203, -60.8458) knots 0 0 0 0 0.063155 0.138394 0.138394 0.138394 0.138394
  spline S84 degree 3 poles (59.7203, -60.8458) (59.4679, -60.8516) (59.0185, -60.862) (58.6339, -61.0902) (58.4652, -61.1903) knots 0 0 0 0 0.074172 0.132094 0.132094 0.132094 0.132094
  spline S85 degree 3 poles (58.4652, -61.1903) (58.3459, -61.3067) (58.1167, -61.5302) (58.0756, -61.8468) (58.0559, -61.9986) knots 0 0 0 0 0.048408 0.092998 0.092998 0.092998 0.092998
  spline S86 degree 3 poles (58.0559, -61.9986) (58.0717, -62.1304) (58.1037, -62.3972) (58.312, -62.5674) (58.4175, -62.6535) knots 0 0 0 0 0.038259 0.077458 0.077458 0.077458 0.077458
  spline S87 degree 3 poles (58.4175, -62.6535) (58.5629, -62.7188) (58.9664, -62.9) (59.3971, -63.0034) (59.6726, -63.0696) knots 0 0 0 0 0.047763 0.132466 0.132466 0.132466 0.132466
  spline S88 degree 3 poles (59.6726, -63.0696) (60.0569, -63.1658) (60.6932, -63.3252) (61.3034, -63.5648) (61.545, -63.6596) knots 0 0 0 0 0.118683 0.196494 0.196494 0.196494 0.196494
  spline S89 degree 3 poles (61.545, -63.6596) (61.707, -63.7482) (62.0214, -63.9202) (62.2335, -64.2087) (62.3363, -64.3486) knots 0 0 0 0 0.054633 0.106055 0.106055 0.106055 0.106055
  spline S90 degree 3 poles (62.3363, -64.3486) (62.4149, -64.4998) (62.5733, -64.8047) (62.5949, -65.1477) (62.6057, -65.3206) knots 0 0 0 0 0.050517 0.101865 0.101865 0.101865 0.101865
  spline S91 degree 3 poles (62.6057, -65.3206) (62.5968, -65.4784) (62.5791, -65.7914) (62.4487, -66.0764) (62.384, -66.2176) knots 0 0 0 0 0.046969 0.093127 0.093127 0.093127 0.093127
  spline S92 degree 3 poles (62.384, -66.2176) (62.3034, -66.3494) (62.1421, -66.613) (61.901, -66.8064) (61.7804, -66.9031) knots 0 0 0 0 0.045957 0.091962 0.091962 0.091962 0.091962
  spline S93 degree 3 poles (61.7804, -66.9031) (61.6697, -66.9728) (61.4254, -67.1265) (61.1499, -67.2136) (60.9993, -67.2613) knots 0 0 0 0 0.039078 0.086233 0.086233 0.086233 0.086233
  spline S94 degree 3 poles (60.9993, -67.2613) (60.8294, -67.304) (60.4812, -67.3916) (60.1223, -67.4024) (59.9386, -67.4079) knots 0 0 0 0 0.052412 0.10736 0.10736 0.10736 0.10736
  spline S95 degree 3 poles (59.9386, -67.4079) (59.6696, -67.4001) (59.1592, -67.3852) (58.6718, -67.2339) (58.4413, -67.1623) knots 0 0 0 0 0.0803 0.152356 0.152356 0.152356 0.152356
  spline S96 degree 3 poles (58.4413, -67.1623) (58.2451, -67.0792) (57.88, -66.9245) (57.6132, -66.6324) (57.4898, -66.4973) knots 0 0 0 0 0.063037 0.117311 0.117311 0.117311 0.117311
  spline S97 degree 3 poles (57.4898, -66.4973) (57.3942, -66.3374) (57.1861, -65.9894) (57.1087, -65.5907) (57.0668, -65.3752) knots 0 0 0 0 0.055458 0.120727 0.120727 0.120727 0.120727
  line L35 (57.0668, -65.3752) -> (58.2674, -65.2115)
  spline S98 degree 3 poles (58.2674, -65.2115) (58.3053, -65.3858) (58.3788, -65.7235) (58.6233, -65.9669) (58.7415, -66.0846) knots 0 0 0 0 0.052286 0.10125 0.10125 0.10125 0.10125
  spline S99 degree 3 poles (58.7415, -66.0846) (58.8953, -66.1759) (59.2356, -66.3778) (59.6325, -66.3911) (59.8499, -66.3984) knots 0 0 0 0 0.052851 0.116857 0.116857 0.116857 0.116857
  spline S100 degree 3 poles (59.8499, -66.3984) (60.097, -66.3964) (60.5227, -66.3929) (60.8993, -66.1997) (61.0573, -66.1187) knots 0 0 0 0 0.072813 0.125434 0.125434 0.125434 0.125434
  spline S101 degree 3 poles (61.0573, -66.1187) (61.1626, -66.0255) (61.3619, -65.8492) (61.4006, -65.5873) (61.4188, -65.4638) knots 0 0 0 0 0.040702 0.076975 0.076975 0.076975 0.076975
  spline S102 degree 3 poles (61.4188, -65.4638) (61.4125, -65.3861) (61.3997, -65.2299) (61.3125, -65.0996) (61.2688, -65.0341) knots 0 0 0 0 0.022989 0.046195 0.046195 0.046195 0.046195
  spline S103 degree 3 poles (61.2688, -65.0341) (61.2076, -64.9695) (61.0738, -64.828) (60.8952, -64.7494) (60.7981, -64.7067) knots 0 0 0 0 0.026422 0.05785 0.05785 0.05785 0.05785
  spline S104 degree 3 poles (60.7981, -64.7067) (60.6772, -64.6686) (60.3182, -64.5555) (59.9546, -64.4577) (59.7135, -64.3929) knots 0 0 0 0 0.038027 0.112916 0.112916 0.112916 0.112916
  spline S105 degree 3 poles (59.7135, -64.3929) (59.3426, -64.2944) (58.7281, -64.1312) (58.132, -63.9107) (57.8956, -63.8233) knots 0 0 0 0 0.115025 0.190592 0.190592 0.190592 0.190592
  spline S106 degree 3 poles (57.8956, -63.8233) (57.7344, -63.7427) (57.419, -63.5851) (57.1962, -63.3121) (57.0873, -63.1787) knots 0 0 0 0 0.053404 0.104439 0.104439 0.104439 0.104439
  spline S107 degree 3 poles (57.0873, -63.1787) (57.0018, -63.0242) (56.8213, -62.6979) (56.8034, -62.3247) (56.794, -62.1282) knots 0 0 0 0 0.052263 0.110368 0.110368 0.110368 0.110368
  spline S108 degree 3 poles (56.794, -62.1282) (56.8098, -61.9253) (56.8419, -61.513) (57.0477, -61.1542) (57.1521, -60.972) knots 0 0 0 0 0.06027 0.122395 0.122395 0.122395 0.122395
  spline S109 degree 3 poles (57.1521, -60.972) (57.2883, -60.8) (57.5701, -60.4439) (57.9758, -60.2389) (58.1855, -60.133) knots 0 0 0 0 0.065008 0.13454 0.13454 0.13454 0.13454
  spline S110 degree 3 poles (58.1855, -60.133) (58.423, -60.0465) (58.9163, -59.8668) (59.4412, -59.8467) (59.7135, -59.8363) knots 0 0 0 0 0.075327 0.156499 0.156499 0.156499 0.156499
  line L36 (78.6767, -64.4407) -> (78.6767, -60)
  line L37 (78.6767, -60) -> (80, -60)
  line L38 (80, -60) -> (80, -70)
  line L39 (80, -70) -> (75.5662, -70)
  spline S111 degree 3 poles (75.5662, -70) (75.1711, -69.997) (74.4812, -69.9917) (73.8172, -69.8087) (73.5334, -69.7306) knots 0 0 0 0 0.11786 0.20582 0.20582 0.20582 0.20582
  spline S112 degree 3 poles (73.5334, -69.7306) (73.3119, -69.6215) (72.8605, -69.3993) (72.5697, -68.9883) (72.4216, -68.779) knots 0 0 0 0 0.072838 0.148429 0.148429 0.148429 0.148429
  spline S113 degree 3 poles (72.4216, -68.779) (72.3002, -68.5445) (72.0554, -68.0714) (72.0222, -67.5397) (72.0055, -67.2715) knots 0 0 0 0 0.078283 0.157922 0.157922 0.157922 0.157922
  spline S114 degree 3 poles (72.0055, -67.2715) (72.0322, -66.9328) (72.085, -66.2662) (72.4935, -65.7375) (72.6944, -65.4775) knots 0 0 0 0 0.099557 0.195925 0.195925 0.195925 0.195925
  spline S115 degree 3 poles (72.6944, -65.4775) (72.9754, -65.2541) (73.5995, -64.7579) (74.3888, -64.6236) (74.8226, -64.5498) knots 0 0 0 0 0.106045 0.235514 0.235514 0.235514 0.235514
  spline S116 degree 3 poles (74.8226, -64.5498) (74.665, -64.4719) (74.3823, -64.3322) (74.1343, -64.1378) (74.0246, -64.0518) knots 0 0 0 0 0.052575 0.094289 0.094289 0.094289 0.094289
  spline S117 degree 3 poles (74.0246, -64.0518) (73.8301, -63.8576) (73.4216, -63.4494) (73.0966, -62.9719) (72.9263, -62.7217) knots 0 0 0 0 0.082274 0.172834 0.172834 0.172834 0.172834
  line L40 (72.9263, -62.7217) -> (71.1869, -60)
  line L41 (71.1869, -60) -> (72.8513, -60)
  line L42 (72.8513, -60) -> (74.1746, -62.0805)
  spline S118 degree 3 poles (74.1746, -62.0805) (74.3476, -62.3477) (74.6514, -62.8171) (74.9856, -63.2653) (75.1296, -63.4584) knots 0 0 0 0 0.095446 0.167688 0.167688 0.167688 0.167688
  spline S119 degree 3 poles (75.1296, -63.4584) (75.2425, -63.5995) (75.4414, -63.848) (75.6928, -64.0427) (75.8015, -64.1269) knots 0 0 0 0 0.053958 0.095073 0.095073 0.095073 0.095073
  spline S120 degree 3 poles (75.8015, -64.1269) (75.8993, -64.1853) (76.0896, -64.299) (76.302, -64.3622) (76.4052, -64.3929) knots 0 0 0 0 0.034032 0.0662 0.0662 0.0662 0.0662
  spline S121 degree 3 poles (76.4052, -64.3929) (76.504, -64.4067) (76.7482, -64.4408) (76.9949, -64.4407) (77.1419, -64.4407) knots 0 0 0 0 0.029888 0.073901 0.073901 0.073901 0.073901
  line L43 (77.1419, -64.4407) -> (78.6767, -64.4407)
  circle A0 centre (98, -30) radius 1.5
  circle A1 centre (78, 74.5) radius 2
  circle A2 centre (35, -22) radius 2
  circle A3 centre (98, 30) radius 1.5
  circle A4 centre (63.3562, -86.2251) radius 2
  circle A5 centre (-95, -95) radius 2
  circle A6 centre (72, 15) radius 2
  circle A7 centre (72, -22) radius 2
  circle A8 centre (35, 15) radius 2
  circle A9 centre (-35, 15) radius 2
  circle A10 centre (8.4631, -37.4313) radius 2
  circle A11 centre (63.3562, -38.9561) radius 2
  circle A12 centre (30, -98) radius 1.5
  line L44 (-3, 13) -> (3, 13)
  line L45 (3, 13) -> (3, -20)
  line L46 (3, -20) -> (-3, -20)
  line L47 (-3, -20) -> (-3, 13)
  circle A13 centre (-98, 30) radius 1.5
  circle A14 centre (-95, 95) radius 2
  circle A15 centre (-72, 15) radius 2
  circle A16 centre (-35, -22) radius 2
  circle A17 centre (95, 95) radius 2
  circle A18 centre (-72, -22) radius 2
  circle A19 centre (8.768, -86.5301) radius 2
  circle A20 centre (69.71, 37.5753) radius 2
  circle A21 centre (-30, -98) radius 1.5
  circle A22 centre (-98, -30) radius 1.5
  circle A23 centre (95, -95) radius 2
  line L48 (100, 100) -> (20, 100)
  line L49 (20, 100) -> (20, 80)
  line L50 (20, 80) -> (-20, 80)
  line L51 (-20, 80) -> (-20, 100)
  line L52 (-20, 100) -> (-100, 100)
  line L53 (-100, 100) -> (-100, -100)
  line L54 (-100, -100) -> (100, -100)
  line L55 (100, -100) -> (100, 100)
  line L56 (64.3765, -2.0621) -> (64.3765, -1)
  line L57 (64.3765, -1) -> (70, -1)
  line L58 (70, -1) -> (70, -10)
  line L59 (70, -10) -> (68.809, -10)
  line L60 (68.809, -10) -> (68.809, -2.0621)
  line L61 (68.809, -2.0621) -> (64.3765, -2.0621)
  line L62 (40.8513, -8.0723) -> (40.8513, -1)
  line L63 (40.8513, -1) -> (41.9932, -1)
  line L64 (41.9932, -1) -> (41.9932, -10)
  line L65 (41.9932, -10) -> (40.7715, -10)
  line L66 (40.7715, -10) -> (36.0443, -2.9338)
  line L67 (36.0443, -2.9338) -> (36.0443, -10)
  line L68 (36.0443, -10) -> (34.9025, -10)
  line L69 (34.9025, -10) -> (34.9025, -1)
  line L70 (34.9025, -1) -> (36.1241, -1)
  line L71 (36.1241, -1) -> (40.8513, -8.0723)
  spline S122 degree 3 poles (46.2415, -10.0368) (45.909, -10.0168) (45.2726, -9.9784) (44.7504, -9.6149) (44.501, -9.4413) knots 0 0 0 0 0.097755 0.187143 0.187143 0.187143 0.187143
  spline S123 degree 3 poles (44.501, -9.4413) (44.2967, -9.2168) (43.8694, -8.7472) (43.7499, -8.1222) (43.6876, -7.796) knots 0 0 0 0 0.089283 0.186745 0.186745 0.186745 0.186745
  line L72 (43.6876, -7.796) -> (44.7865, -7.7101)
  spline S124 degree 3 poles (44.7865, -7.7101) (44.8332, -7.9032) (44.9158, -8.2444) (45.1167, -8.5311) (45.204, -8.6555) knots 0 0 0 0 0.058927 0.104154 0.104154 0.104154 0.104154
  spline S125 degree 3 poles (45.204, -8.6555) (45.3623, -8.7934) (45.6797, -9.0698) (46.0989, -9.1087) (46.309, -9.1282) knots 0 0 0 0 0.061322 0.122937 0.122937 0.122937 0.122937
  spline S126 degree 3 poles (46.309, -9.1282) (46.4785, -9.1168) (46.8118, -9.0943) (47.0962, -8.9195) (47.236, -8.8336) knots 0 0 0 0 0.050118 0.098579 0.098579 0.098579 0.098579
  spline S127 degree 3 poles (47.236, -8.8336) (47.4031, -8.6862) (47.756, -8.375) (47.9543, -7.9475) (48.0587, -7.7224) knots 0 0 0 0 0.066092 0.1396 0.1396 0.1396 0.1396
  spline S128 degree 3 poles (48.0587, -7.7224) (48.1467, -7.4291) (48.3502, -6.7516) (48.364, -6.0431) (48.3718, -5.6412) knots 0 0 0 0 0.091462 0.21132 0.21132 0.21132 0.21132
  spline S129 degree 3 poles (48.3718, -5.6412) (48.2344, -5.8291) (47.9678, -6.194) (47.5825, -6.4295) (47.3956, -6.5437) knots 0 0 0 0 0.069073 0.134091 0.134091 0.134091 0.134091
  spline S130 degree 3 poles (47.3956, -6.5437) (47.2017, -6.6296) (46.8161, -6.8004) (46.3953, -6.8257) (46.1862, -6.8383) knots 0 0 0 0 0.063087 0.125376 0.125376 0.125376 0.125376
  spline S131 degree 3 poles (46.1862, -6.8383) (45.8309, -6.8038) (45.1168, -6.7343) (44.5762, -6.2621) (44.3046, -6.0249) knots 0 0 0 0 0.104296 0.209632 0.209632 0.209632 0.209632